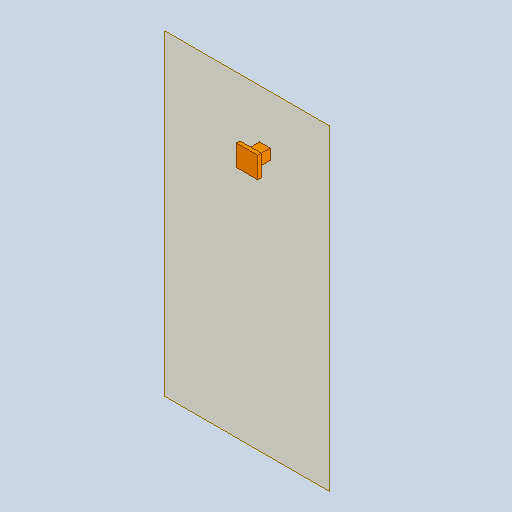
# Autodesk Inventor part: кнопка
Saved by Autodesk Inventor 2024.2 (Build 282272000, 272)
## iProperties
Created: 2026-10-02
Part Number: кнопка
Material: PA-CF
Document SubType Name: Modeling
Designer: katya_notebook
Density: 1.2 g/cm^3
Appearance: Типовые
Author: katya_notebook
Autodesk Inventor part; units mm, degrees
ref_plane "YZ Plane" through (0, 0, 0) normal (1, 0, 0) x (0, 1, 0)
ref_plane "XZ Plane" through (0, 0, 0) normal (0, 1, 0) x (-1, 0, 0)
ref_plane "XY Plane" through (0, 0, 0) normal (0, 0, 1) x (1, 0, 0)
ref_plane "РабПлоскость1" through (0, 0, 5) normal (0, 0, 1) x (1, 0, 0)
sketch "Эскиз1" plane through (0, 0, 5) normal (0, 0, 1) x (1, 0, 0)
  line L0 (-3.5, 52.2672) -> (-3.5, 45.2672) projected
  line L1 (-3.5, 45.2672) -> (3.5, 45.2672) projected
  line L2 (3.5, 45.2672) -> (3.5, 52.2672) projected
  line L3 (3.5, 52.2672) -> (-3.5, 52.2672) projected
  line L4 (-3.5, 52.2672) -> (3.5, 45.2672)
  line L5 (3.5, 52.2672) -> (-3.5, 45.2672)
  line L6 (3, 45.7672) -> (-3, 45.7672)
  line L7 (-3, 45.7672) -> (-3, 51.7672)
  line L8 (-3, 51.7672) -> (3, 51.7672)
  line L9 (3, 51.7672) -> (3, 45.7672)
  line L10 (3, 45.7672) -> (-3, 51.7672) construction
  line L11 (-3, 45.7672) -> (3, 51.7672) construction
  point P0 (0, 0)
  point P1 (0, 48.7672)
  dimension "d0" = 6
  constraints: 16 end point, 3 midpoint, 2 parallel, 2 perpendicular, 1 horizontal, 1 point on line
  measures "d0" distance of L6.end L7.end
extrude "Выдавливание1" add sketch "Эскиз1" against normal blind 10 contours L8 L5 L4 | L4 L5 L7 | L5 L4 L6 | L9 L4 L5
sketch "Эскиз2" plane through (0, 0, 5) normal (0, 0, 1) x (1, 0, 0)
  line L0 (-3, 51.7672) -> (3, 51.7672) projected
  line L1 (-3, 45.7672) -> (-3, 51.7672) projected
  line L2 (3, 51.7672) -> (-3, 45.7672)
  line L3 (-3, 45.7672) -> (3, 45.7672)
  line L4 (3, 45.7672) -> (-3, 51.7672)
  line L5 (-6, 42.7672) -> (6, 42.7672)
  line L6 (6, 42.7672) -> (6, 54.7672)
  line L7 (6, 54.7672) -> (-6, 54.7672)
  line L8 (-6, 54.7672) -> (-6, 42.7672)
  line L9 (-6, 42.7672) -> (6, 54.7672) construction
  line L10 (6, 42.7672) -> (-6, 54.7672) construction
  point P0 (0, 0)
  point P1 (0, 48.7672)
  dimension "d3" = 12
  constraints: 18 end point, 3 midpoint, 3 perpendicular, 2 parallel, 1 horizontal, 1 point on line
  measures "d3" distance of L5.end L6.end
extrude "Выдавливание2" add sketch "Эскиз2" against normal blind 2 contours L4 L2 L1 | L0 L2 L4 | L2 L4 L3 | L8 L7 L6 L5
sketch "Эскиз4" plane through (0, 0, -5) normal (0, 0, -1) x (-1, 0, 0)
  line L0 (3, 45.7672) -> (3, 51.7672) projected
  line L1 (-3, 45.7672) -> (3, 45.7672) projected
  line L2 (3, 51.7672) -> (-3, 51.7672)
  line L3 (-3, 51.7672) -> (-3, 45.7672)
  line L4 (-3, 45.7672) -> (3, 45.7672)
  line L5 (3, 45.7672) -> (3, 51.7672)
  line L6 (3, 51.7672) -> (-3, 45.7672)
  line L7 (-3, 51.7672) -> (3, 45.7672)
  line L8 (-1.5, 47.2672) -> (1.5, 47.2672)
  line L9 (1.5, 47.2672) -> (1.5, 50.2672)
  line L10 (1.5, 50.2672) -> (-1.5, 50.2672)
  line L11 (-1.5, 50.2672) -> (-1.5, 47.2672)
  line L12 (-1.5, 47.2672) -> (1.5, 50.2672) construction
  line L13 (1.5, 47.2672) -> (-1.5, 50.2672) construction
  point P0 (0, 0)
  point P1 (0, 48.7672)
  dimension "d6" = 1.5
  constraints: 24 end point, 4 parallel, 3 midpoint, 3 perpendicular, 2 horizontal, 1 point on line
  measures "d6" distance between parallel lines of L0 L9
extrude "Выдавливание3" cut sketch "Эскиз4" against normal blind 5 contours L8 L6 L7 | L7 L6 L9 | L6 L7 L10 | L11 L7 L6
